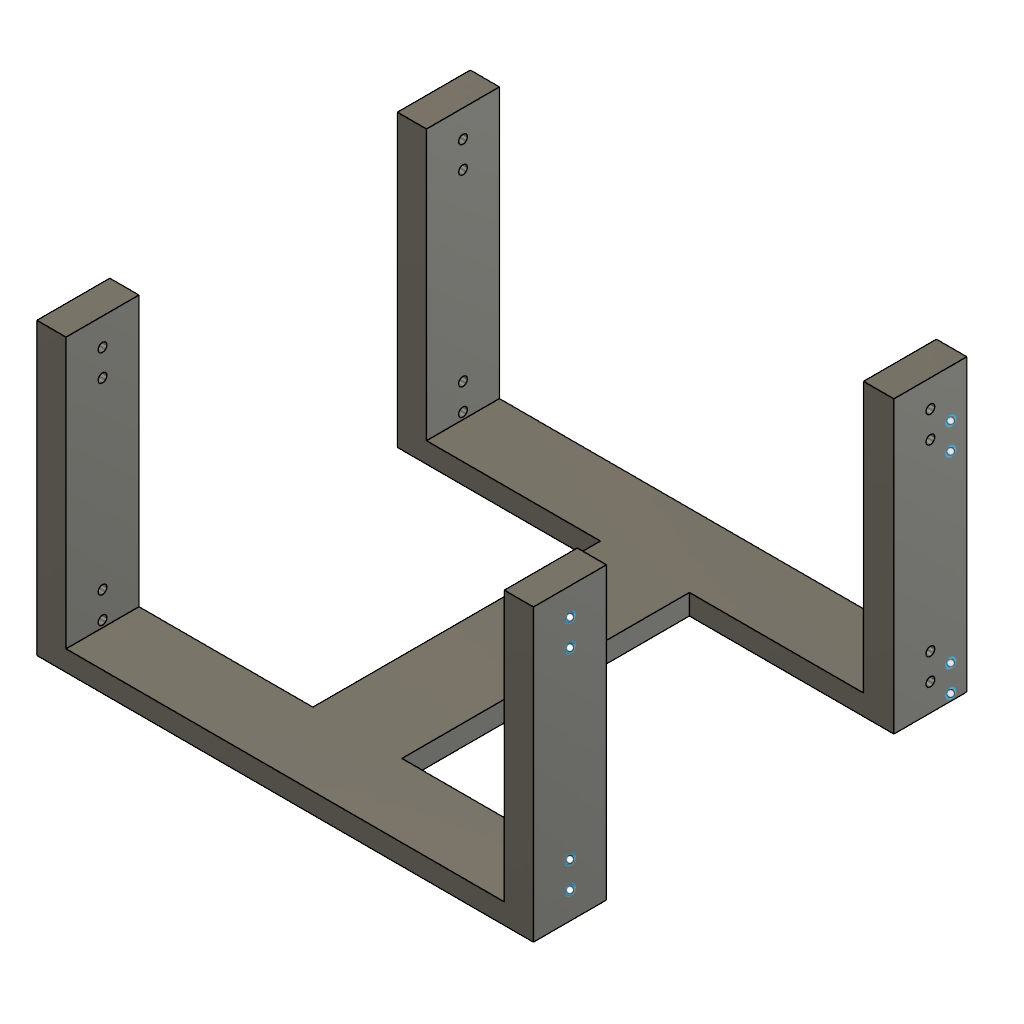
body (Autodesk Fusion 360 design; units mm, degrees)
part number: 2026-10-09-00-02-01-781
Autodesk Fusion 360 part; units mm, degrees
sketch "Sketch1" plane through (0, 0, 0) normal (0, 1, 0) x (1, 0, 0)
  line L0 (-100, 20) -> (70, 20)
  line L1 (70, 20) -> (70, -5)
  line L2 (70, -5) -> (-100, -5)
  line L3 (-100, -5) -> (-100, 20)
  line L4 (-100, 143.4) -> (70, 143.4)
  line L5 (70, 143.4) -> (70, 118.4)
  line L6 (70, 118.4) -> (-100, 118.4)
  line L7 (-100, 118.4) -> (-100, 143.4)
  line L8 (-30.487, 118.4) -> (0, 118.4)
  line L9 (0, 118.4) -> (0, 20)
  line L10 (0, 20) -> (-30.487, 20)
  line L11 (-30.487, 20) -> (-30.487, 118.4)
  dimension "d1" = 170
  dimension "d2" = 25
  dimension "d3" = 170
  dimension "d4" = 25
  dimension "d5" = 98.4
  dimension "d6" = 148.4
  dimension "d7" = 69.513
  dimension "d8" = 70
  constraint horizontal L0
  constraint vertical L1
  constraint horizontal L2
  constraint vertical L3
  constraint horizontal L4
  constraint vertical L5
  constraint horizontal L6
  constraint vertical L7
  constraint horizontal L8
  constraint vertical L9
  constraint horizontal L10
  constraint vertical L11
  constraint coincident L0 L9.end
  constraint coincident L6 L8.start
  measures "d1" distance of L0.start L0.end
  measures "d2" distance of L0.start L2.end
  measures "d3" distance of L4.start L4.end
  measures "d4" distance of L4.start L6.end
  measures "d5" distance of L0 L6
  measures "d6" distance of L2 L4
  measures "d7" distance of L6.end L8.start
  measures "d8" distance of L5.end L8.end
extrude "Extrude1" add sketch "Sketch1" along normal blind 7
sketch "Sketch2" plane through (0, 7, 0) normal (0, 1, 0) x (-1, 0, 0)
  line L0 (30.487, -20) -> (100, -20)
  line L1 (100, -20) -> (100, 5)
  line L2 (100, 5) -> (-70, 5)
  line L3 (-70, 5) -> (-70, -20)
  line L4 (-70, -20) -> (0, -20)
  line L5 (0, -20) -> (0, -118.4)
  line L6 (0, -118.4) -> (-70, -118.4)
  line L7 (-70, -118.4) -> (-70, -143.4)
  line L8 (-70, -143.4) -> (100, -143.4)
  line L9 (100, -143.4) -> (100, -118.4)
  line L10 (100, -118.4) -> (30.487, -118.4)
  line L11 (30.487, -118.4) -> (30.487, -20)
  line L12 (-60, -20) -> (-70, -20)
  line L13 (-70, -20) -> (-70, 5)
  line L14 (-70, 5) -> (-60, 5)
  line L15 (-60, 5) -> (-60, -20)
  line L16 (100, -20) -> (90, -20)
  line L17 (90, -20) -> (90, 5)
  line L18 (90, 5) -> (100, 5)
  line L19 (100, 5) -> (100, -20)
  line L20 (100, -143.4) -> (90, -143.4)
  line L21 (90, -143.4) -> (90, -118.4)
  line L22 (90, -118.4) -> (100, -118.4)
  line L23 (100, -118.4) -> (100, -143.4)
  line L24 (-70, -143.4) -> (-59.5678, -143.4)
  line L25 (-59.5678, -143.4) -> (-59.5678, -118.4)
  line L26 (-59.5678, -118.4) -> (-70, -118.4)
  line L27 (-70, -118.4) -> (-70, -143.4)
  constraint horizontal L12
  constraint vertical L13
  constraint horizontal L14
  constraint vertical L15
  constraint coincident L2.end L3.start
  constraint coincident L4 L12.start
  constraint horizontal L16
  constraint vertical L17
  constraint horizontal L18
  constraint vertical L19
  constraint coincident L2 L17.end
  constraint coincident L0.end L1.start
  constraint horizontal L20
  constraint vertical L21
  constraint horizontal L22
  constraint vertical L23
  constraint coincident L10 L21.end
  constraint coincident L8.end L9.start
  constraint horizontal L24
  constraint vertical L25
  constraint horizontal L26
  constraint vertical L27
  constraint coincident L6 L25.end
  constraint coincident L7.end L8.start
extrude "Extrude2" add sketch "Sketch2" along normal blind 92.4 contours L0 L1 L2 L16 L17 L18 L19 | L8 L9 L10 L20 L21 L22 L23 | L2 L3 L4 L12 L13 L14 L15 | L6 L7 L8 L24 L25 L26 L27
sketch "sketch 951" plane through (76.9436, 0, 0) normal (1, 0, 0) x (0, 0, -1)
  circle A0 centre (130.9, 90.1226) radius 1.5
  circle A1 centre (130.9, 81.0776) radius 1.5
extrude "Extrude3" cut sketch "sketch 951" against normal blind 230
sketch "sketch 968" plane through (76.9436, 0, 0) normal (1, 0, 0) x (0, 0, -1)
  circle A0 centre (130.9, 18.3224) radius 1.5
  circle A1 centre (130.9, 9.2774) radius 1.5
extrude "Extrude4" cut sketch "sketch 968" against normal blind 220
sketch "sketch 984" plane through (70, 0, 0) normal (1, 0, 0) x (0, 0, -1)
  circle A0 centre (7.5, 18.3224) radius 1.5
  circle A1 centre (7.5, 18.3224) radius 1.5
  circle A2 centre (7.5, 90.1226) radius 1.5
  circle A3 centre (7.5, 90.1226) radius 1.5
  circle A4 centre (7.5, 81.0776) radius 1.5
  circle A5 centre (7.5, 81.0776) radius 1.5
  circle A6 centre (7.5, 9.2774) radius 1.5
  circle A7 centre (7.5, 9.2774) radius 1.5
extrude "Extrude5" cut sketch "sketch 984" against normal blind 210
